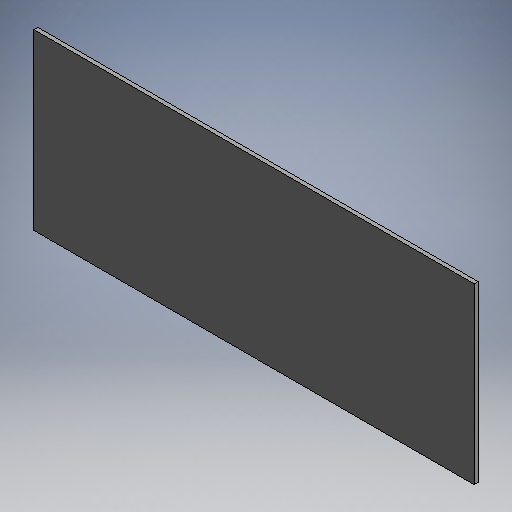
# Autodesk Inventor part: Factory_Floor
Saved by Autodesk Inventor 2026.2 (Build 302298000, 298)
## iProperties
Part Number: Factory_Floor
Material: Generic
Document SubType Name: Modeling
Designer: Jacob
Appearance: Default
Author: Jacob
Autodesk Inventor part; units mm, degrees
ref_plane "YZ Plane" through (0, 0, 0) normal (1, 0, 0) x (0, 1, 0)
ref_plane "XZ Plane" through (0, 0, 0) normal (0, 1, 0) x (-1, 0, 0)
ref_plane "XY Plane" through (0, 0, 0) normal (0, 0, 1) x (1, 0, 0)
sketch "Sketch1" plane through (0, 0, 0) normal (0, 0, 1) x (1, 0, 0)
  line L0 (-1000, -1000) -> (15876.4, -1000)
  line L1 (15876.4, -1000) -> (15876.4, 5665.6)
  line L2 (15876.4, 5665.6) -> (-1000, 5665.6)
  line L3 (-1000, 5665.6) -> (-1000, -1000)
  constraints: 8 end point, 2 parallel, 1 horizontal, 1 perpendicular
extrude "Extrusion1" add sketch "Sketch1" against normal blind 150
body "Solid1"
